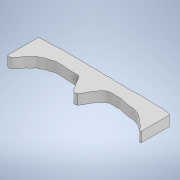
# Autodesk Inventor part: batman
Saved by Autodesk Inventor 2022.6 (Build 266554000, 554)
## iProperties
Created: 2024-11-29
Part Number: batman
Material: Generic
Document SubType Name: Modeling
Designer: Dragos Macovei
Density: 1 g/cm^3
Appearance: Default
Author: Dragos Macovei
Autodesk Inventor part; units mm, degrees
ref_plane "YZ Plane" through (0, 0, 0) normal (1, 0, 0) x (0, 1, 0)
ref_plane "XZ Plane" through (0, 0, 0) normal (0, 1, 0) x (-1, 0, 0)
ref_plane "XY Plane" through (0, 0, 0) normal (0, 0, 1) x (1, 0, 0)
sketch "Sketch1" plane through (0, 0, 0) normal (0, 1, 0) x (-1, 0, 0)
  line L0 (0, 0) -> (40, 0)
  line L1 (40, 0) -> (40, 40)
  line L2 (40, 40) -> (0, 40)
  line L3 (0, 40) -> (0, 0)
  line L4 (-198.75, 333.9209) -> (207.65, 333.9209) construction
  line L5 (207.65, 333.9209) -> (207.65, -207.9458) construction
  line L6 (207.65, -207.9458) -> (-198.75, -207.9458) construction
  line L7 (-198.75, -207.9458) -> (-198.75, 333.9209) construction
  spline S0 degree 5 poles (19.4445, 24.1463) (19.2271, 23.9929) (18.9085, 23.6072) (18.5994, 22.7317) (17.997, 21.834) (17.2372, 20.3988) (16.4401, 19.9049) (15.4664, 18.3204) (13.2361, 19.2498) (11.993, 18.4341) (10.8631, 19.2352) (9.8454, 19.1514) (8.0709, 19.7764) (7.7486, 19.3013) (5.1784, 20.1514) (4.604, 20.4824) (2.5831, 22.2691) (1.9182, 22.864) (0.7874, 23.4094) (1.0031, 24.6691) (-0.1679, 24.3398) (-0.403, 24.274) (-1.2897, 23.3649) (-0.5559, 22.659) (-0.4617, 21.7563) (-0.447, 20.23) (-0.4352, 19.5503) (0.0689, 17.4144) (-0.7901, 15.8388) (1.1535, 15.5368) (1.9609, 15.1677) (3.9205, 15.4078) (5.6738, 15.0891) (7.8709, 15.3554) (9.1023, 14.8114) (13.3938, 15.5422) (13.8608, 14.8742) (17.6026, 15.4723) (18.0123, 14.7827) (20.5187, 15.377) (21.9812, 14.8397) (24.0223, 15.24) (25.9905, 14.952) (27.6493, 15.0524) (29.661, 14.8547) (31.064, 15.2378) (32.5488, 14.7634) (34.5563, 15.1263) (35.0899, 15.0691) (36.5225, 15.2525) (37.8367, 15.162) (38.2764, 15.2704) (40.9906, 15.2676) (40.2882, 15.8012) (40.7613, 16.3969) (40.0125, 17.1884) (40.3774, 18.2353) (40.3241, 19.1412) (40.3081, 20.3212) (40.3267, 21.3139) (40.2943, 22.3071) (40.4097, 23.5075) (40.3816, 24.2162) (39.8116, 25.01) (38.7545, 24.6933) (38.1334, 24.0252) (37.4644, 23.1034) (37.0145, 21.9792) (35.7097, 21.5584) (35.6644, 20.3621) (34.4167, 20.6168) (33.7869, 19.5956) (33.0042, 19.728) (32.1562, 19.3724) (31.0983, 18.9082) (30.7019, 19.0376) (27.7121, 18.9792) (26.9816, 19.3375) (23.4638, 19.1326) (23.9031, 19.4195) (22.8829, 20.3861) (22.5934, 21.6226) (21.8389, 22.0542) (21.2064, 23.5003) (20.7764, 24.1285) (20.3597, 24.3652) (19.8814, 24.3726) (19.5954, 24.2527) (19.4445, 24.1463) knots 0 0 0 0 0 0 0.014962 0.024845 0.037324 0.050516 0.063587 0.076284 0.088986 0.101577 0.113074 0.124956 0.137402 0.15082 0.164143 0.177595 0.189879 0.201097 0.210581 0.219574 0.228314 0.237412 0.247268 0.257851 0.269616 0.281987 0.294518 0.306902 0.319725 0.332492 0.345757 0.359782 0.375462 0.391402 0.407715 0.42342 0.438976 0.45345 0.467967 0.482133 0.496839 0.511602 0.52611 0.540413 0.554395 0.567414 0.579854 0.592011 0.603905 0.61567 0.626687 0.636809 0.646476 0.655775 0.664687 0.674722 0.685503 0.696651 0.707891 0.718766 0.729083 0.739095 0.748957 0.758877 0.769383 0.780488 0.791646 0.802758 0.813645 0.823904 0.833786 0.843708 0.853383 0.86419 0.876645 0.890173 0.903019 0.916091 0.928307 0.93934 0.949973 0.961081 0.97171 0.981796 0.989613 1 1 1 1 1 1
  point P0 (18.0208, 21.8187)
  point P1 (17.2411, 20.6202)
  point P2 (16.4758, 19.7683)
  point P3 (15.2917, 18.9164)
  point P4 (13.2413, 18.873)
  point P5 (11.855, 18.8008)
  point P6 (10.8442, 19.0608)
  point P7 (9.7179, 19.2918)
  point P8 (8.4039, 19.5373)
  point P9 (7.5519, 19.5662)
  point P10 (5.7614, 20.0001)
  point P11 (4.3174, 20.7935)
  point P12 (2.5412, 22.2953)
  point P13 (1.5593, 23.0462)
  point P14 (0.9673, 23.8115)
  point P15 (0.6207, 24.3746)
  point P16 (0, 24.3746)
  point P17 (-0.4623, 24.1463)
  point P18 (-0.9099, 23.5083)
  point P19 (-0.7655, 22.7719)
  point P20 (-0.5055, 21.8477)
  point P21 (-0.4477, 20.5482)
  point P22 (-0.3611, 19.4363)
  point P23 (-0.2311, 17.3858)
  point P24 (-0.1156, 16.0718)
  point P25 (0.8663, 15.5519)
  point P26 (1.9926, 15.3208)
  point P27 (3.5809, 15.2919)
  point P28 (5.5591, 15.2196)
  point P29 (7.4652, 15.1907)
  point P30 (9.4434, 15.0896)
  point P31 (12.8368, 15.2339)
  point P32 (14.7429, 15.1473)
  point P33 (17.241, 15.1762)
  point P34 (18.4395, 15.0606)
  point P35 (20.2301, 15.1329)
  point P36 (22.0206, 15.0462)
  point P37 (23.9845, 15.0896)
  point P38 (25.9917, 15.0319)
  point P39 (27.8111, 14.9886)
  point P40 (29.6739, 14.9887)
  point P41 (31.1612, 15.0465)
  point P42 (32.8652, 14.9455)
  point P43 (34.4681, 15.061)
  point P44 (35.2767, 15.1188)
  point P45 (36.4752, 15.1911)
  point P46 (37.6593, 15.2056)
  point P47 (39.06, 15.2634)
  point P48 (40.4896, 15.5522)
  point P49 (40.5185, 15.8554)
  point P50 (40.5185, 16.3175)
  point P51 (40.3019, 17.0539)
  point P52 (40.273, 18.0791)
  point P53 (40.3307, 19.1332)
  point P54 (40.3162, 20.2884)
  point P55 (40.3162, 21.3424)
  point P56 (40.3306, 22.4398)
  point P57 (40.3739, 23.5516)
  point P58 (40.2295, 24.2736)
  point P59 (39.7529, 24.7357)
  point P60 (38.9732, 24.6635)
  point P61 (38.2224, 24.0715)
  point P62 (37.5437, 23.1185)
  point P63 (36.7784, 22.0933)
  point P64 (35.8976, 21.2847)
  point P65 (35.36, 20.6569)
  point P66 (34.5071, 20.3227)
  point P67 (33.7003, 19.8155)
  point P68 (33.0202, 19.6311)
  point P69 (32.2134, 19.3891)
  point P70 (31.4065, 19.0894)
  point P71 (30.7034, 18.9972)
  point P72 (28.4457, 19.0565)
  point P73 (25.8698, 19.2244)
  point P74 (23.8648, 19.3408)
  point P75 (23.5949, 19.5982)
  point P76 (23.0973, 20.3445)
  point P77 (22.5127, 21.4142)
  point P78 (21.8468, 22.3099)
  point P79 (21.0817, 23.6168)
  point P80 (20.6354, 24.1463)
  point P81 (20.1455, 24.3322)
  point P82 (0, 15.9455)
  point P83 (40, 15.3425)
  point P84 (40, 24.5853)
  dimension "d0" = 40
  dimension "d1" = 40
  constraints: 8 end point, 2 parallel, 1 horizontal, 1 perpendicular, 1 point on line, 86 other
  measures "d0" distance of L2.end L1.end
  measures "d1" distance of L1.end L0.end
extrude "Extrusion1" add sketch "Sketch1" along normal blind 3 contours L3 S0 L1
body "Solid1"
